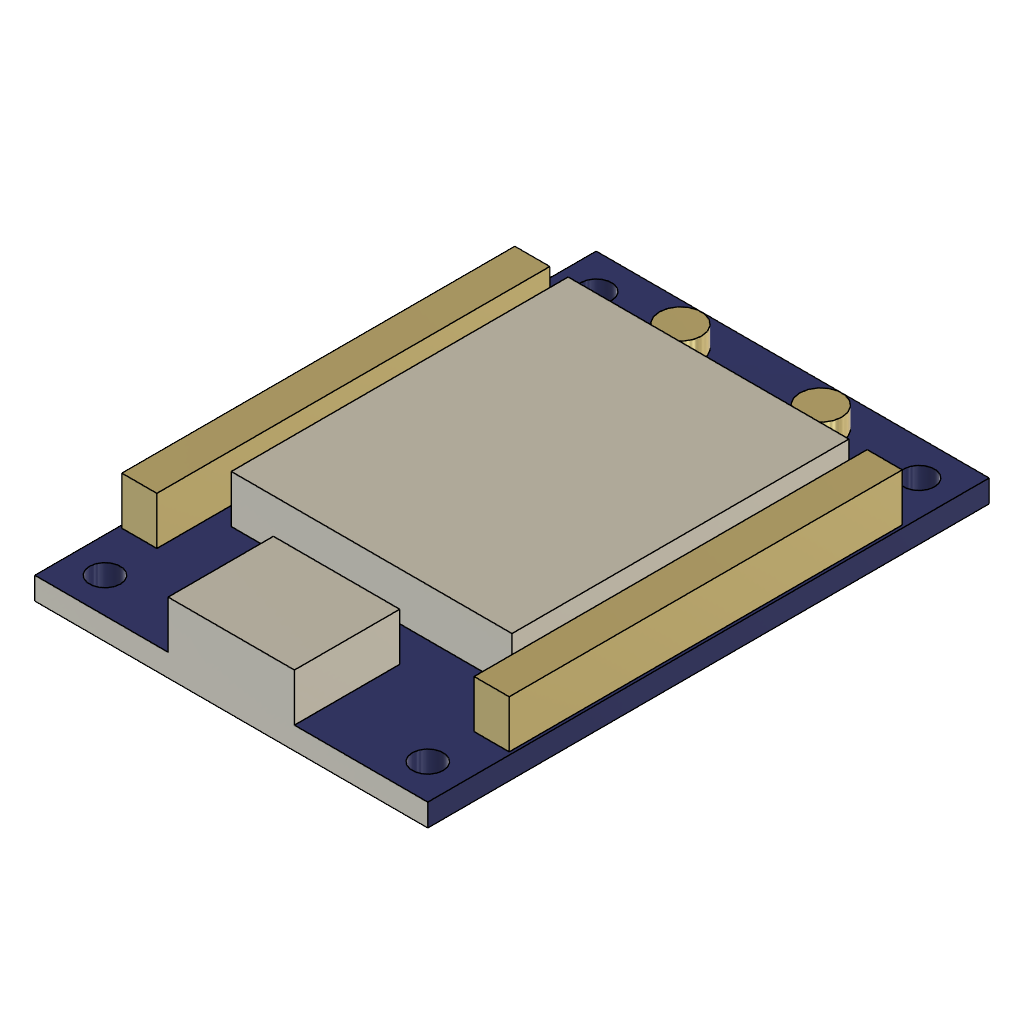
A767S 2 (Autodesk Fusion 360 design; units mm, degrees)
part number: 2026-10-25-01-18-46-468
Autodesk Fusion 360 part; units mm, degrees
sketch "Sketch1" plane through (0, 0, 0) normal (0, 0, 1) x (1, 0, 0)
  line L0 (-14, -20) -> (14, -20)
  line L1 (14, -20) -> (14, 20)
  line L2 (14, 20) -> (-14, 20)
  line L3 (-14, 20) -> (-14, -20)
extrude "Extrude1" add sketch "Sketch1" along normal blind 1.6
sketch "Sketch2" plane through (0, 0, 0) normal (0, 0, 1) x (1, 0, 0)
  circle A0 centre (-11.5, -17.5) radius 1.1
extrude "Extrude2" cut sketch "Sketch2" along normal blind 2
sketch "Sketch3" plane through (0, 0, 0) normal (0, 0, 1) x (1, 0, 0)
  circle A0 centre (11.5, -17.5) radius 1.1
extrude "Extrude3" cut sketch "Sketch3" along normal blind 2
sketch "Sketch4" plane through (0, 0, 0) normal (0, 0, 1) x (1, 0, 0)
  circle A0 centre (-11.5, 17.5) radius 1.1
extrude "Extrude4" cut sketch "Sketch4" along normal blind 2
sketch "Sketch5" plane through (0, 0, 0) normal (0, 0, 1) x (1, 0, 0)
  circle A0 centre (11.5, 17.5) radius 1.1
extrude "Extrude5" cut sketch "Sketch5" along normal blind 2
sketch "Sketch6" plane through (0, 0, 0) normal (0, 0, 1) x (1, 0, 0)
  line L0 (-10, -10) -> (10, -10)
  line L1 (10, -10) -> (10, 14)
  line L2 (10, 14) -> (-10, 14)
  line L3 (-10, 14) -> (-10, -10)
extrude "Extrude6" add sketch "Sketch6" along normal blind 3.4 from surface at 1.6
sketch "Sketch7" plane through (0, 0, 0) normal (0, 0, 1) x (1, 0, 0)
  line L0 (-4.5, -20) -> (4.5, -20)
  line L1 (4.5, -20) -> (4.5, -12.5)
  line L2 (4.5, -12.5) -> (-4.5, -12.5)
  line L3 (-4.5, -12.5) -> (-4.5, -20)
extrude "Extrude7" add sketch "Sketch7" along normal blind 3.4 from surface at 1.6
sketch "Sketch8" plane through (0, 0, 0) normal (0, 0, 1) x (1, 0, 0)
  line L0 (-13.8, -14) -> (-11.3, -14)
  line L1 (-11.3, -14) -> (-11.3, 14)
  line L2 (-11.3, 14) -> (-13.8, 14)
  line L3 (-13.8, 14) -> (-13.8, -14)
extrude "Extrude8" add sketch "Sketch8" along normal blind 3.4 from surface at 1.6
sketch "Sketch9" plane through (0, 0, 0) normal (0, 0, 1) x (1, 0, 0)
  line L0 (11.3, -14) -> (13.8, -14)
  line L1 (13.8, -14) -> (13.8, 14)
  line L2 (13.8, 14) -> (11.3, 14)
  line L3 (11.3, 14) -> (11.3, -14)
extrude "Extrude9" add sketch "Sketch9" along normal blind 3.4 from surface at 1.6
sketch "Sketch10" plane through (0, 0, 0) normal (0, 0, 1) x (1, 0, 0)
  circle A0 centre (-5, 17) radius 1.5
extrude "Extrude10" add sketch "Sketch10" along normal blind 1.5 from surface at 1.6
sketch "Sketch11" plane through (0, 0, 0) normal (0, 0, 1) x (1, 0, 0)
  circle A0 centre (5, 17) radius 1.5
extrude "Extrude11" add sketch "Sketch11" along normal blind 1.5 from surface at 1.6
